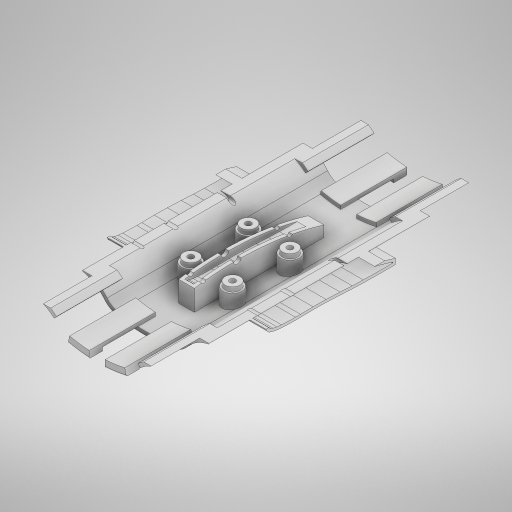
# Autodesk Inventor part: ENCASTRE_FUSELAJE
Saved by Autodesk Inventor 2023 (Build 270158000, 158)
## iProperties
Created: 2023-05-19
Part Number: ENCASTRE_FUSELAJE
Material: Genérico
Document SubType Name: Modeling
Designer: brand
Density: 1 g/cm^3
Appearance: Valor por defecto
Author: brand
Autodesk Inventor part; units mm, degrees
ref_plane "XZ Plane" through (0, 0, 0) normal (0, 1, 0) x (-1, 0, 0)
ref_plane "XY Plane" through (0, 0, 0) normal (0, 0, 1) x (1, 0, 0)
sketch "Boceto1" plane through (0, 0, 0) normal (0, 0, 1) x (1, 0, 0)
  line L0 (-27.5, 0) -> (27.5, 0) construction
  arc A0 (33, 24.3875) -> (-33, 24.3875) centre (0, -121.9375) ccw
  arc A1 (-33, -24.3875) -> (33, -24.3875) centre (0, 121.9375) ccw
  arc A2 (-70.9258, 0.9771) -> (-46.9085, 15.7579) centre (-80, 42.625) ccw
  arc A3 (-46.9085, -15.7579) -> (-70.9258, -0.9771) centre (-80, -42.625) ccw
  line L1 (0, 28.0625) -> (0, -28.0625) construction
  arc A4 (46.9085, 15.7579) -> (70.9258, 0.9771) centre (80, 42.625) ccw
  arc A5 (70.9258, -0.9771) -> (46.9085, -15.7579) centre (80, -42.625) ccw
  arc A6 (-33, 24.3875) -> (-46.9085, 15.7579) centre (-27.5, 0) ccw
  arc A7 (-46.9085, -15.7579) -> (-33, -24.3875) centre (-27.5, 0) ccw
  arc A8 (33, -24.3875) -> (46.9085, -15.7579) centre (27.5, 0) ccw
  arc A9 (46.9085, 15.7579) -> (33, 24.3875) centre (27.5, 0) ccw
  arc A10 (32.12, 20.4855) -> (-32.12, 20.4855) centre (0, -121.9375) ccw
  arc A11 (43.8031, 13.2366) -> (32.12, 20.4855) centre (27.5, 0) ccw
  arc A12 (43.8031, 13.2366) -> (61.1056, 0) centre (80, 42.625) ccw
  arc A13 (61.1056, 0) -> (43.8031, -13.2366) centre (80, -42.625) ccw
  arc A14 (32.12, -20.4855) -> (43.8031, -13.2366) centre (27.5, 0) ccw
  arc A15 (-32.12, -20.4855) -> (32.12, -20.4855) centre (0, 121.9375) ccw
  arc A16 (-43.8031, -13.2366) -> (-32.12, -20.4855) centre (-27.5, 0) ccw
  arc A17 (-43.8031, -13.2366) -> (-61.1056, 0) centre (-80, -42.625) ccw
  arc A18 (-61.1056, 0) -> (-43.8031, 13.2366) centre (-80, 42.625) ccw
  arc A19 (-32.12, 20.4855) -> (-43.8031, 13.2366) centre (-27.5, 0) ccw
  arc A20 (-70.9258, 0.9771) -> (-70.9258, -0.9771) centre (-70.7129, 0) ccw
  arc A21 (70.9258, -0.9771) -> (70.9258, 0.9771) centre (70.7129, 0) ccw
  point P0 (0, 0)
  point P1 (0, 0)
  point P2 (0, 0)
  dimension "d0" = 300
  dimension "d1" = 55
  dimension "d2" = 80
  dimension "d3" = 80
  dimension "d4" = 4
  dimension "d5" = 1
  constraints: 46 point on circle, 22 centre point, 6 tangent, 5 symmetric about line, 4 end point, 2 horizontal alignment, 1 coincident, 1 equal radius, 1 horizontal, 1 midpoint, 9 other
  measures "d0" diameter of A0
  measures "d1" distance of L0.start L0.end
  measures "d2" horizontal distance of point (0, 0) A18.centre
  measures "d3" horizontal distance of point (0, 0) A17.centre
  measures "d4" radial gap between concentric circles of A0 A10
  measures "d5" radius of A20
extrude "Extrusión1" add sketch "Boceto1" against normal blind 170
sketch "Boceto2" plane through (0, 0, 0) normal (1, 0, 0) x (0, 1, 0)
  arc A0 (-6.3235, -149.5277) -> (5.972, -101.1613) centre (-420.6839, -18.4451) ccw
  arc A1 (5.972, -101.1613) -> (11.3027, -54.4805) centre (-297.3284, -42.8809) ccw
  arc A2 (11.3027, -54.4805) -> (11.0641, -38.2325) centre (-144.1615, -48.6381) ccw
  arc A3 (11.0641, -38.2325) -> (7.9803, -20.5332) centre (-74.6379, -44.046) ccw
  arc A4 (7.9803, -20.5332) -> (5.1635, -13.545) centre (-27.6939, -30.851) ccw
  arc A5 (5.1635, -13.545) -> (2.6711, -10.3705) centre (-4.0493, -18.2127) ccw
  arc A6 (2.6711, -10.3705) -> (1.0881, -9.7136) centre (0.7764, -12.7005) ccw
  arc A7 (1.0881, -9.7136) -> (0, -10) centre (1.0887, -11.926) ccw
  arc A8 (0, -10) -> (-1.8033, -12.1262) centre (2.0348, -13.5536) ccw
  arc A9 (-1.8033, -12.1262) -> (-2.4847, -14.2967) centre (17.2896, -19.3122) ccw
  arc A10 (-2.4847, -14.2967) -> (-3.4173, -18.7476) centre (27.4031, -22.8823) ccw
  arc A11 (-3.4173, -18.7476) -> (-3.9308, -23.8416) centre (82.0127, -29.9326) ccw
  arc A12 (-3.9308, -23.8416) -> (-4.4581, -39.76) centre (210.5667, -38.9149) ccw
  line L0 (-4.4581, -39.76) -> (-4.4203, -45.4494)
  line L1 (-4.4203, -45.4494) -> (-4.1974, -59.6715)
  arc A13 (-4.3725, -74.4621) -> (-4.1974, -59.6715) centre (-320.6036, -63.321) ccw
  arc A14 (-5.0686, -90.3774) -> (-4.3725, -74.4621) centre (-890.267, -43.6885) ccw
  line L2 (-5.0686, -90.3774) -> (-5.78, -104.0138)
  arc A15 (-5.78, -104.0138) -> (-6.2063, -116.5233) centre (482.8669, -126.9256) ccw
  arc A16 (-6.2063, -116.5233) -> (-6.4633, -149.5204) centre (962.6143, -140.5689) ccw
  line L3 (-6.4633, -149.5204) -> (-6.3235, -149.5277)
  line L4 (0, 0) -> (0, -170) projected
  arc A17 (-4.4295, -23.8064) -> (-4.9581, -39.7626) centre (210.5667, -38.9149) ccw
  arc A18 (-3.9129, -18.6819) -> (-4.4295, -23.8064) centre (82.0127, -29.9326) ccw
  arc A19 (-2.9674, -14.1662) -> (-3.9129, -18.6819) centre (27.4031, -22.8823) ccw
  arc A20 (-2.2716, -11.951) -> (-2.9674, -14.1662) centre (17.2896, -19.3122) ccw
  arc A21 (-0.2473, -9.5654) -> (-2.2716, -11.951) centre (2.0348, -13.5536) ccw
  arc A22 (1.1143, -9.2137) -> (-0.2473, -9.5654) centre (1.0887, -11.926) ccw
  arc A23 (2.9917, -9.9868) -> (1.1143, -9.2137) centre (0.7764, -12.7005) ccw
  arc A24 (5.6077, -13.3155) -> (2.9917, -9.9868) centre (-4.0493, -18.2127) ccw
  arc A25 (8.4609, -20.3953) -> (5.6077, -13.3155) centre (-27.6939, -30.851) ccw
  arc A26 (11.563, -38.1989) -> (8.4609, -20.3953) centre (-74.6379, -44.046) ccw
  arc A27 (11.8023, -54.5016) -> (11.563, -38.1989) centre (-144.1615, -48.6381) ccw
  arc A28 (6.4629, -101.256) -> (11.8023, -54.5016) centre (-297.3284, -42.8809) ccw
  arc A29 (-5.9636, -150.0472) -> (6.4629, -101.256) centre (-420.6839, -18.4451) ccw
  line L5 (-5.9636, -150.0472) -> (-6.9588, -149.9951)
  arc A30 (-6.7061, -116.5118) -> (-6.9588, -149.9951) centre (962.6143, -140.5689) ccw
  arc A31 (-6.2794, -103.9891) -> (-6.7061, -116.5118) centre (482.8669, -126.9256) ccw
  line L6 (-6.2794, -103.9891) -> (-5.5679, -90.3513)
  arc A32 (-5.5679, -90.3513) -> (-4.8722, -74.4446) centre (-890.267, -43.6885) ccw
  arc A33 (-4.8722, -74.4446) -> (-4.6973, -59.6783) centre (-320.6036, -63.321) ccw
  line L7 (-4.6973, -59.6783) -> (-4.9203, -45.455)
  line L8 (-4.9203, -45.455) -> (-4.9581, -39.7626)
  line L9 (1.1143, -9.2137) -> (-24.0625, -9.2137) construction
  line L10 (-24.0625, -170) -> (-24.0625, 0) projected
  line L11 (-5.9636, -150.0472) -> (-24.0625, -150.0472) construction
  circle A34 centre (-336.4534, -54.4805) radius 340 construction
  line L12 (-24.0625, -6.2137) -> (24.3875, -6.2137)
  line L13 (24.3875, 0) -> (24.3875, -170) projected
  line L14 (-24.0625, -153.0472) -> (24.3875, -153.0472)
  circle A35 centre (1.7519, -16.7828) radius 2.25
  circle A36 centre (3.3626, -54.9049) radius 4.25
  circle A37 centre (-1.8171, -114.7492) radius 2.25
  point P0 (0, -10)
  dimension "d8" = 10
  dimension "d9" = 0.5
  dimension "d11" = 680
  dimension "d12" = 336.4534
  dimension "d13" = 54.4805
  dimension "d14" = 3
  dimension "d15" = 3
  dimension "d16" = 150.0472
  dimension "d19" = 4.5
  dimension "d20" = 8.5
  dimension "d21" = 4.5
  dimension "d22" = 16.7828
  dimension "d23" = 1.7519
  dimension "d24" = 54.9049
  dimension "d25" = 3.3626
  dimension "d26" = 114.7492
  dimension "d27" = 1.8171
  constraints: 68 point on circle, 38 centre point, 24 end point, 6 point on line, 3 horizontal, 1 perpendicular, 20 other
  measures "d8" distance of L4.start point (0, -10)
  measures "d9" radial gap between concentric circles of A12 A17
  measures "d11" diameter of A34
  measures "d12" horizontal distance of A34.centre L4.start
  measures "d13" vertical distance of A34.centre L4.start
  measures "d14" distance between parallel lines of L12 L9
  measures "d15" distance between parallel lines of L14 L11
  measures "d16" distance from line of L11 L4.start
  measures "d19" diameter of A35
  measures "d20" diameter of A36
  measures "d21" diameter of A37
  measures "d22" vertical distance of A35.centre L4.start
  measures "d23" horizontal distance of A35.centre L4.start
  measures "d24" vertical distance of A36.centre L4.start
  measures "d25" horizontal distance of A36.centre L4.start
  measures "d26" vertical distance of A37.centre L4.start
  measures "d27" horizontal distance of A37.centre L4.start
extrude "Extrusión2" add sketch "Boceto2" along normal mid plane 10 contours A29 A28 A27 A26 A25 A24 A23 A22 L4 L12 L13 L14 | L4 L14 L10 L12 A22 A21 A20 A19 A18 A17 L8 L7 A33 A32 L6 A31 A30 L5 A29
sketch "Boceto3" plane through (5, 0, 0) normal (1, 0, 0) x (0, 0, -1)
  line L0 (153.0472, 23.9769) -> (6.2137, 23.9769) projected
  line L1 (6.2137, -23.9769) -> (153.0472, -23.9769) projected
  line L2 (6.2137, -23.9769) -> (6.2137, 23.9769) projected
  line L3 (153.0472, 23.9769) -> (153.0472, -23.9769) projected
  circle A0 centre (16.783, 1.752) radius 2.6
  circle A1 centre (54.905, 3.363) radius 4.25
  circle A2 centre (114.749, -1.817) radius 2.6
  arc A3 (150.0472, -5.9636) -> (101.256, 6.4629) centre (18.4451, -420.6839) ccw projected
  arc A4 (101.256, 6.4629) -> (54.5016, 11.8023) centre (42.8809, -297.3284) ccw projected
  arc A5 (54.5016, 11.8023) -> (38.1989, 11.563) centre (48.6381, -144.1615) ccw projected
  arc A6 (38.1989, 11.563) -> (20.3953, 8.4609) centre (44.046, -74.6379) ccw projected
  arc A7 (20.3953, 8.4609) -> (13.3155, 5.6077) centre (30.851, -27.6939) ccw projected
  arc A8 (13.3155, 5.6077) -> (9.9868, 2.9917) centre (18.2127, -4.0493) ccw projected
  arc A9 (9.9868, 2.9917) -> (9.2137, 1.1143) centre (12.7005, 0.7764) ccw projected
  arc A10 (9.2137, 1.1143) -> (9.5654, -0.2473) centre (11.926, 1.0887) ccw projected
  arc A11 (9.5654, -0.2473) -> (11.951, -2.2716) centre (13.5536, 2.0348) ccw projected
  arc A12 (11.951, -2.2716) -> (14.1662, -2.9674) centre (19.3122, 17.2896) ccw projected
  arc A13 (14.1662, -2.9674) -> (18.6819, -3.9129) centre (22.8823, 27.4031) ccw projected
  arc A14 (18.6819, -3.9129) -> (23.8064, -4.4295) centre (29.9326, 82.0127) ccw projected
  arc A15 (23.8064, -4.4295) -> (39.7626, -4.9581) centre (38.9149, 210.5667) ccw projected
  arc A16 (150.0472, -5.9636) -> (101.256, 6.4629) centre (18.4451, -420.6839) ccw projected
  arc A17 (101.256, 6.4629) -> (54.5016, 11.8023) centre (42.8809, -297.3284) ccw projected
  arc A18 (54.5016, 11.8023) -> (38.1989, 11.563) centre (48.6381, -144.1615) ccw projected
  arc A19 (38.1989, 11.563) -> (20.3953, 8.4609) centre (44.046, -74.6379) ccw projected
  arc A20 (20.3953, 8.4609) -> (13.3155, 5.6077) centre (30.851, -27.6939) ccw projected
  arc A21 (13.3155, 5.6077) -> (9.9868, 2.9917) centre (18.2127, -4.0493) ccw projected
  arc A22 (9.9868, 2.9917) -> (9.2137, 1.1143) centre (12.7005, 0.7764) ccw projected
  arc A23 (9.2137, 1.1143) -> (9.5654, -0.2473) centre (11.926, 1.0887) ccw projected
  arc A24 (9.5654, -0.2473) -> (11.951, -2.2716) centre (13.5536, 2.0348) ccw projected
  arc A25 (11.951, -2.2716) -> (14.1662, -2.9674) centre (19.3122, 17.2896) ccw projected
  arc A26 (14.1662, -2.9674) -> (18.6819, -3.9129) centre (22.8823, 27.4031) ccw projected
  arc A27 (18.6819, -3.9129) -> (23.8064, -4.4295) centre (29.9326, 82.0127) ccw projected
  arc A28 (23.8064, -4.4295) -> (39.7626, -4.9581) centre (38.9149, 210.5667) ccw projected
  line L4 (39.7626, -4.9581) -> (45.455, -4.9203) projected
  line L5 (45.455, -4.9203) -> (59.6783, -4.6973) projected
  arc A29 (74.4446, -4.8722) -> (59.6783, -4.6973) centre (63.321, -320.6036) ccw projected
  arc A30 (90.3513, -5.5679) -> (74.4446, -4.8722) centre (43.6885, -890.267) ccw projected
  line L6 (90.3513, -5.5679) -> (103.9891, -6.2794) projected
  arc A31 (103.9891, -6.2794) -> (116.5118, -6.7061) centre (126.9256, 482.8669) ccw projected
  arc A32 (116.5118, -6.7061) -> (149.9951, -6.9588) centre (140.5689, 962.6143) ccw projected
  line L7 (149.9951, -6.9588) -> (150.0472, -5.9636) projected
  line L8 (153.0472, 23.9769) -> (6.2137, 23.9769) projected
  line L9 (153.0472, 23.9769) -> (153.0472, -23.9769) projected
  line L10 (6.2137, -23.9769) -> (153.0472, -23.9769) projected
  line L11 (6.2137, -23.9769) -> (6.2137, 23.9769) projected
  point P0 (0, 0)
  dimension "d28" = 5.2
  dimension "d29" = 8.5
  dimension "d30" = 5.2
  dimension "d31" = 16.783
  dimension "d32" = 1.752
  dimension "d33" = 3.363
  dimension "d34" = 54.905
  dimension "d35" = 114.749
  dimension "d36" = 1.817
  constraints: 3 centre point
  measures "d28" diameter of A0
  measures "d29" diameter of A1
  measures "d30" diameter of A2
  measures "d31" horizontal distance of point (0, 0) A0.centre
  measures "d32" vertical distance of point (0, 0) A0.centre
  measures "d33" vertical distance of point (0, 0) A1.centre
  measures "d34" horizontal distance of point (0, 0) A1.centre
  measures "d35" horizontal distance of point (0, 0) A2.centre
  measures "d36" vertical distance of point (0, 0) A2.centre
extrude "Extrusión3" add sketch "Boceto3" along normal blind 4 contours L3 L1 L2 L0 | L7 A32 A31 L6 A30 A29 L5 L4 A15 A14 A13 A12 A11 A10 A9 A8 A7 A6 A5 A4 A3
mirror "Simetría1" about plane through (0, 0, 0) normal (1, 0, 0) of "Extrusión3"
sketch "Boceto4" plane through (0, 0, 0) normal (1, 0, 0) x (0, 1, 0)
  circle A0 centre (1.752, -16.783) radius 2.6 projected
  circle A1 centre (3.363, -54.905) radius 4.25 projected
  circle A2 centre (-1.817, -114.749) radius 2.6 projected
  point P0 (0, 0)
extrude "Extrusión4" cut sketch "Boceto4" along normal through all both and the other way through all
sketch "Boceto5" plane through (0, 0, 0) normal (0, 1, 0) x (-1, 0, 0)
  circle A0 centre (-23.62, -99.8876) radius 8.5
  line L0 (32.12, -170) -> (-32.12, -170) projected
  line L1 (-33, -170) -> (33, -170) projected
  line L2 (0, -170) -> (0, 0)
  line L3 (9, -153.0472) -> (-9, -153.0472) projected
  line L4 (-9, -153.0472) -> (-9, -6.2137) projected
  line L5 (-9, -6.2137) -> (9, -6.2137) projected
  line L6 (9, -6.2137) -> (9, -153.0472) projected
  line L7 (-32.12, 0) -> (32.12, 0) projected
  line L8 (-32.12, 0) -> (-32.12, -170) projected
  line L9 (32.12, -170) -> (-32.12, -170) projected
  line L10 (32.12, 0) -> (32.12, -170) projected
  circle A1 centre (-23.62, -34.8116) radius 8.5
  circle A2 centre (23.62, -99.8876) radius 8.5
  circle A3 centre (23.62, -34.8116) radius 8.5
  circle A4 centre (-23.62, -99.8876) radius 3.25
  circle A5 centre (-23.62, -34.8116) radius 3.25
  circle A6 centre (23.62, -99.8876) radius 3.25
  circle A7 centre (23.62, -34.8116) radius 3.25
  dimension "d41" = 17
  dimension "d42" = 6.5
  dimension "d43" = 6.5
  constraints: 8 centre point, 4 symmetric about line, 2 coincident, 2 end point, 2 tangent, 1 equal radius, 1 midpoint, 1 vertical, 4 other
  measures "d41" diameter of A0
  measures "d42" diameter of A4
  measures "d43" diameter of A5
extrude "Extrusión5" add sketch "Boceto5" along normal mid plane 20 contours A0 | A1 | A2 | A3
sketch "Boceto6" plane through (23.62, 10, -34.8116) normal (0, 1, 0) x (1, 0, 0)
  circle A0 centre (0, 0) radius 3.25 projected
  line L0 (-3.1754, 5.5) -> (3.1754, 5.5)
  line L1 (3.1754, 5.5) -> (6.3509, 0)
  line L2 (6.3509, 0) -> (3.1754, -5.5)
  line L3 (3.1754, -5.5) -> (-3.1754, -5.5)
  line L4 (-3.1754, -5.5) -> (-6.3509, 0)
  line L5 (-6.3509, 0) -> (-3.1754, 5.5)
  circle A1 centre (0, 0) radius 10.5
  line L6 (-23.62, -34.8116) -> (-23.62, 135.1884)
  line L7 (9.38, 135.1884) -> (-56.62, 135.1884) projected
  circle A2 centre (0, 65.076) radius 3.25 projected
  line L8 (0, 65.076) -> (0, 0)
  line L9 (0, 32.538) -> (-50.0066, 32.538)
  circle A3 centre (0, 65.076) radius 3.25
  line L10 (-3.1754, 59.576) -> (3.1754, 59.576)
  line L11 (3.1754, 59.576) -> (6.3509, 65.076)
  line L12 (6.3509, 65.076) -> (3.1754, 70.576)
  line L13 (3.1754, 70.576) -> (-3.1754, 70.576)
  line L14 (-3.1754, 70.576) -> (-6.3509, 65.076)
  line L15 (-6.3509, 65.076) -> (-3.1754, 59.576)
  circle A4 centre (0, 65.076) radius 10.5
  circle A5 centre (-47.24, 0) radius 3.25
  line L16 (-44.0646, 5.5) -> (-50.4154, 5.5)
  line L17 (-50.4154, 5.5) -> (-53.5909, 0)
  line L18 (-53.5909, 0) -> (-50.4154, -5.5)
  line L19 (-50.4154, -5.5) -> (-44.0646, -5.5)
  line L20 (-44.0646, -5.5) -> (-40.8891, 0)
  line L21 (-40.8891, 0) -> (-44.0646, 5.5)
  circle A6 centre (-47.24, 0) radius 10.5
  circle A7 centre (-47.24, 65.076) radius 3.25
  line L22 (-47.24, 65.076) -> (-47.24, 0)
  line L23 (-50.4154, 59.576) -> (-53.5909, 65.076)
  line L24 (-40.8891, 65.076) -> (-44.0646, 59.576)
  circle A8 centre (-47.24, 65.076) radius 3.25
  line L25 (-53.5909, 65.076) -> (-50.4154, 70.576)
  line L26 (-50.4154, 70.576) -> (-44.0646, 70.576)
  line L27 (-44.0646, 70.576) -> (-40.8891, 65.076)
  circle A9 centre (-47.24, 65.076) radius 10.5
  line L28 (-44.0646, 59.576) -> (-50.4154, 59.576)
  point P0 (0, 5.5)
  point P1 (0, 59.576)
  point P2 (-47.24, 5.5)
  point P3 (-47.24, 32.538)
  point P4 (-47.24, 59.576)
  dimension "d46" = 11
  dimension "d47" = 11
  dimension "d48" = 11
  dimension "d49" = 120
  dimension "d50" = 120
  dimension "d51" = 21
  constraints: 56 end point, 27 symmetric about line, 8 centre point, 4 coincident, 3 midpoint, 3 parallel, 2 horizontal, 1 equal length, 1 horizontal alignment, 1 vertical, 1 vertical alignment, 7 other
  measures "d46" distance between parallel lines of L3 L0
  measures "d47" distance between parallel lines of L4 L1
  measures "d48" distance between parallel lines of L5 L2
  measures "d49" angle of L5 L0
  measures "d50" angle of L2 L1
  measures "d51" diameter of A1
extrude "Extrusión6" add sketch "Boceto6" along normal through all contours A1 | A4 | A6 | A9
sketch "Boceto7" plane through (-23.62, 10, -34.8116) normal (0, -1, 0) x (1, 0, 0)
  line L0 (-6.3509, 0) -> (-3.1754, -5.5) projected
  line L1 (-3.1754, -5.5) -> (3.1754, -5.5) projected
  line L2 (3.1754, -5.5) -> (6.3509, 0) projected
  line L3 (6.3509, 0) -> (3.1754, 5.5) projected
  line L4 (3.1754, 5.5) -> (-3.1754, 5.5) projected
  line L5 (-3.1754, 5.5) -> (-6.3509, 0) projected
  line L6 (40.8891, 0) -> (44.0646, -5.5) projected
  line L7 (44.0646, -5.5) -> (50.4154, -5.5) projected
  line L8 (50.4154, -5.5) -> (53.5909, 0) projected
  line L9 (53.5909, 0) -> (50.4154, 5.5) projected
  line L10 (50.4154, 5.5) -> (44.0646, 5.5) projected
  line L11 (44.0646, 5.5) -> (40.8891, 0) projected
  line L12 (53.5909, -65.076) -> (50.4154, -59.576) projected
  line L13 (50.4154, -59.576) -> (44.0646, -59.576) projected
  line L14 (44.0646, -59.576) -> (40.8891, -65.076) projected
  line L15 (40.8891, -65.076) -> (44.0646, -70.576) projected
  line L16 (44.0646, -70.576) -> (50.4154, -70.576) projected
  line L17 (50.4154, -70.576) -> (53.5909, -65.076) projected
  line L18 (6.3509, -65.076) -> (3.1754, -59.576) projected
  line L19 (3.1754, -59.576) -> (-3.1754, -59.576) projected
  line L20 (-3.1754, -59.576) -> (-6.3509, -65.076) projected
  line L21 (-6.3509, -65.076) -> (-3.1754, -70.576) projected
  line L22 (-3.1754, -70.576) -> (3.1754, -70.576) projected
  line L23 (3.1754, -70.576) -> (6.3509, -65.076) projected
  point P0 (23.62, 34.8116)
extrude "Extrusión7" cut sketch "Boceto7" against normal through all
sketch "Boceto8" plane through (-23.62, -10, -34.8116) normal (0, -1, 0) x (1, 0, 0)
  circle A0 centre (0, 0) radius 10.5 projected
  circle A1 centre (0, 0) radius 8.5 projected
  circle A2 centre (47.24, 0) radius 10.5 projected
  circle A3 centre (47.24, 0) radius 8.5 projected
  circle A4 centre (47.24, -65.076) radius 10.5 projected
  circle A5 centre (47.24, -65.076) radius 8.5 projected
  circle A6 centre (0, -65.076) radius 10.5 projected
  circle A7 centre (0, -65.076) radius 8.5 projected
  point P0 (23.62, 34.8116)
extrude "Extrusión8" add sketch "Boceto8" against normal blind 5
sketch "Boceto9" plane through (-23.62, -10, -34.8116) normal (0, -1, 0) x (1, 0, 0)
  circle A0 centre (0, 0) radius 8.5 projected
  circle A1 centre (47.24, 0) radius 8.5 projected
  circle A2 centre (47.24, -65.076) radius 8.5 projected
  circle A3 centre (0, -65.076) radius 8.5 projected
  point P0 (23.62, 34.8116)
extrude "Extrusión9" cut sketch "Boceto9" along normal through all
sketch "Boceto10" plane through (-23.62, -10, -34.8116) normal (0, -1, 0) x (1, 0, 0)
  circle A0 centre (0, 0) radius 10.5 projected
  circle A1 centre (47.24, 0) radius 10.5 projected
  circle A2 centre (0, -65.076) radius 10.5 projected
  circle A3 centre (47.24, -65.076) radius 10.5 projected
  circle A4 centre (0, 0) radius 8.5 projected
  circle A5 centre (47.24, 0) radius 10.5 projected
  circle A6 centre (47.24, 0) radius 8.5 projected
  circle A7 centre (47.24, -65.076) radius 10.5 projected
  circle A8 centre (47.24, -65.076) radius 8.5 projected
  circle A9 centre (0, -65.076) radius 10.5 projected
  circle A10 centre (0, -65.076) radius 8.5 projected
  point P0 (23.62, 34.8116)
extrude "Extrusión10" add sketch "Boceto10" along normal through all
sketch "Boceto11" plane through (0, 0, 0) normal (0, 0, 1) x (1, 0, 0)
  line L0 (9, 23.7849) -> (9, -23.7849) projected
  line L1 (-9, 23.7849) -> (-9, -23.7849) projected
  line L2 (9, -23.7849) -> (9, 23.7849) projected
  line L3 (9, 0) -> (83.9061, 0)
  line L4 (83.9061, 0) -> (83.9061, 38.5054)
  line L5 (83.9061, 38.5054) -> (-83.4412, 38.5054)
  line L6 (-83.4412, 38.5054) -> (-83.4412, 0)
  line L7 (-83.4412, 0) -> (-9, 0)
  line L8 (-9, -23.7849) -> (-9, 23.7849) projected
  arc A0 (9, 23.7849) -> (-9, 23.7849) centre (0, -121.9375) ccw projected
  line L9 (-9, 23.7849) -> (-9, -23.7849) projected
  arc A1 (-9, -23.7849) -> (9, -23.7849) centre (0, 121.9375) ccw projected
  line L10 (9, 23.7849) -> (9, -23.7849) projected
  point P0 (0, 0)
  point P1 (-9, 0)
  constraints: 10 end point, 3 perpendicular, 2 midpoint, 1 horizontal, 1 point on line
extrude "Extrusión11" cut sketch "Boceto11" against normal through all contours A0 L1 L7 L6 L5 L4 L3 L0
sketch "Boceto12" plane through (9, 0, 0) normal (1, 0, 0) x (0, 0, -1)
  circle A0 centre (54.481, -336.9415) radius 340
  line L0 (0, 0) -> (0, -0.9771) projected
  line L1 (153.0472, 24.0625) -> (6.2137, 24.0625) projected
  line L2 (6.2137, 23.7849) -> (6.2137, 24.0625) projected
  line L3 (6.2137, 23.7849) -> (6.2137, -23.7849) projected
  line L4 (153.0472, 24.0625) -> (153.0472, 23.7849) projected
  line L5 (153.0472, -23.7849) -> (153.0472, 23.7849) projected
  point P0 (0, -0.4885)
  point P1 (0, -0.4885)
  point P2 (6.2137, -0.3851)
  point P3 (153.0472, -11.5422)
  dimension "d64" = 680
  dimension "d65" = 336.453
  dimension "d66" = 54.481
  constraints: 2 midpoint, 1 centre point
  measures "d64" diameter of A0
  measures "d65" vertical distance of point (0, -0.489) A0.centre
  measures "d66" horizontal distance of point (0, -0.489) A0.centre
extrude "Extrusión12" cut sketch "Boceto12" against normal up to surface (18 mm away) contours A0 L3 L2 L1 L4 L5
ref_plane "Plano de trabajo1" through (90, 0, 0) normal (1, 0, 0) x (0, 1, 0)
sketch "Boceto16" plane through (90, 0, 0) normal (1, 0, 0) x (0, 1, 0)
  arc A0 (0.6889, -14.4103) -> (0.0588, -9.4167) centre (-336.9415, -54.481) ccw projected
  arc A1 (0.0588, -9.4167) -> (-0.2473, -9.5654) centre (1.0887, -11.926) ccw projected
  arc A2 (-0.2473, -9.5654) -> (-2.2716, -11.951) centre (2.0348, -13.5536) ccw projected
  arc A3 (-2.2716, -11.951) -> (-2.9674, -14.1662) centre (17.2896, -19.3122) ccw projected
  arc A4 (-2.9674, -14.1662) -> (-3.9129, -18.6819) centre (27.4031, -22.8823) ccw projected
  arc A5 (-3.9129, -18.6819) -> (-4.4295, -23.8064) centre (82.0127, -29.9326) ccw projected
  arc A6 (-4.4295, -23.8064) -> (-4.9581, -39.7626) centre (210.5667, -38.9149) ccw projected
  line L0 (-4.9581, -39.7626) -> (-4.9203, -45.455) projected
  line L1 (-4.9203, -45.455) -> (-4.6973, -59.6783) projected
  arc A7 (-4.8722, -74.4446) -> (-4.6973, -59.6783) centre (-320.6036, -63.321) ccw projected
  arc A8 (-5.5679, -90.3513) -> (-4.8722, -74.4446) centre (-890.267, -43.6885) ccw projected
  line L2 (-5.5679, -90.3513) -> (-6.2794, -103.9891) projected
  arc A9 (-6.2794, -103.9891) -> (-6.7061, -116.5118) centre (482.8669, -126.9256) ccw projected
  arc A10 (-6.7061, -116.5118) -> (-6.9963, -136.555) centre (962.6143, -140.5689) ccw projected
  arc A11 (-6.9963, -136.555) -> (-2.7704, -117.1679) centre (-336.9415, -54.481) ccw projected
  arc A12 (-1.8679, -112.1495) -> (-2.7704, -117.1679) centre (-1.817, -114.749) ccw projected
  arc A13 (-1.8679, -112.1495) -> (3.0265, -59.1417) centre (-336.9415, -54.481) ccw projected
  arc A14 (3.0371, -50.6675) -> (3.0265, -59.1417) centre (3.363, -54.905) ccw projected
  arc A15 (3.0371, -50.6675) -> (1.2367, -19.3314) centre (-336.9415, -54.481) ccw projected
  arc A16 (0.6889, -14.4103) -> (1.2367, -19.3314) centre (1.752, -16.783) ccw projected
  arc A17 (11.0618, -38.2944) -> (7.978, -20.595) centre (-74.6402, -44.1079) ccw
  arc A18 (7.978, -20.595) -> (5.1612, -13.6069) centre (-27.6962, -30.9129) ccw
  arc A19 (5.1612, -13.6069) -> (2.6688, -10.4324) centre (-4.0517, -18.2746) ccw
  arc A20 (2.6688, -10.4324) -> (0.6236, -9.763) centre (0.7741, -12.7624) ccw
  arc A21 (0.6236, -9.763) -> (0, -10) centre (1.0887, -11.926) ccw
  line L3 (-6.4633, -149.5204) -> (-6.3235, -149.5277)
  arc A22 (-4.4295, -23.8064) -> (-4.9581, -39.7626) centre (210.5667, -38.9149) ccw
  arc A23 (-3.9129, -18.6819) -> (-4.4295, -23.8064) centre (82.0127, -29.9326) ccw
  arc A24 (-2.9674, -14.1662) -> (-3.9129, -18.6819) centre (27.4031, -22.8823) ccw
  arc A25 (-2.2716, -11.951) -> (-2.9674, -14.1662) centre (17.2896, -19.3122) ccw
  arc A26 (-0.2473, -9.5654) -> (-2.2716, -11.951) centre (2.0348, -13.5536) ccw
  arc A27 (0.5586, -9.2659) -> (-0.2473, -9.5654) centre (1.0887, -11.926) ccw
  arc A28 (2.9894, -10.0487) -> (0.5586, -9.2659) centre (0.7741, -12.7624) ccw
  arc A29 (5.6054, -13.3773) -> (2.9894, -10.0487) centre (-4.0517, -18.2746) ccw
  arc A30 (8.4586, -20.4571) -> (5.6054, -13.3773) centre (-27.6962, -30.9129) ccw
  arc A31 (11.5606, -38.2608) -> (8.4586, -20.4571) centre (-74.6402, -44.1079) ccw
  arc A32 (11.8023, -54.501) -> (11.5606, -38.2608) centre (-144.1638, -48.7) ccw
  arc A33 (6.4629, -101.256) -> (11.8023, -54.501) centre (-297.3284, -42.8809) ccw
  arc A34 (-5.9636, -150.0472) -> (6.4629, -101.256) centre (-420.6839, -18.4451) ccw
  line L4 (-5.9636, -150.0472) -> (-6.9588, -149.9951)
  arc A35 (-6.7061, -116.5118) -> (-6.9588, -149.9951) centre (962.6143, -140.5689) ccw
  arc A36 (-6.2794, -103.9891) -> (-6.7061, -116.5118) centre (482.8669, -126.9256) ccw
  line L5 (-6.2794, -103.9891) -> (-5.5679, -90.3513)
  arc A37 (-5.5679, -90.3513) -> (-4.8722, -74.4446) centre (-890.267, -43.6885) ccw
  arc A38 (-4.8722, -74.4446) -> (-4.6973, -59.6783) centre (-320.6036, -63.321) ccw
  line L6 (-4.6973, -59.6783) -> (-4.9203, -45.455)
  line L7 (-4.9203, -45.455) -> (-4.9581, -39.7626)
  line L8 (0.5586, -9.2659) -> (-24.6182, -9.2659) construction
  line L9 (-5.9636, -150.0472) -> (-24.0625, -150.0472) construction
  circle A39 centre (-336.4534, -54.4805) radius 340 construction
  line L10 (-24.6182, -6.2659) -> (23.8318, -6.2659)
  line L11 (-24.0625, -153.0472) -> (24.3875, -153.0472)
  circle A40 centre (1.7519, -16.7828) radius 2.25
  circle A41 centre (3.3626, -54.9049) radius 4.25
  circle A42 centre (-1.8171, -114.7492) radius 2.25
  line L12 (0, 0) -> (0, -14.8619) projected
  line L13 (0, 0) -> (0, -169.9982)
  arc A43 (-7.8704, -74.3397) -> (-7.6971, -59.7191) centre (-320.6036, -63.321) ccw
  arc A44 (-8.5638, -90.1941) -> (-7.8704, -74.3397) centre (-890.267, -43.6885) ccw
  line L14 (-8.5638, -90.1941) -> (-9.2758, -103.8407)
  arc A45 (-9.2758, -103.8407) -> (-9.7053, -116.4427) centre (482.8669, -126.9256) ccw
  arc A46 (-9.7053, -116.4427) -> (-9.9272, -152.8436) centre (962.6143, -140.5689) ccw
  line L15 (-9.9272, -152.8436) -> (-3.8117, -153.1641)
  arc A47 (-3.8117, -153.1641) -> (9.4086, -101.8246) centre (-420.6839, -18.4451) ccw
  arc A48 (9.4086, -101.8246) -> (14.8002, -54.6131) centre (-297.3284, -42.8809) ccw
  arc A49 (14.8002, -54.6131) -> (14.5538, -38.059) centre (-144.1638, -48.7) ccw
  arc A50 (14.5538, -38.059) -> (11.3423, -19.6299) centre (-74.6402, -44.1079) ccw
  arc A51 (11.3423, -19.6299) -> (8.2702, -11.9991) centre (-27.6962, -30.9129) ccw
  arc A52 (8.2702, -11.9991) -> (4.9161, -7.749) centre (-4.0517, -18.2746) ccw
  arc A53 (4.9161, -7.749) -> (0.1782, -6.2866) centre (0.7741, -12.7624) ccw
  arc A54 (0.1782, -6.2866) -> (-1.7315, -6.9583) centre (1.0887, -11.926) ccw
  arc A55 (-1.7315, -6.9583) -> (-5.0811, -10.8991) centre (2.0348, -13.5536) ccw
  arc A56 (-5.0811, -10.8991) -> (-5.8635, -13.3824) centre (17.2896, -19.3122) ccw
  arc A57 (-5.8635, -13.3824) -> (-6.8869, -18.2878) centre (27.4031, -22.8823) ccw
  arc A58 (-6.8869, -18.2878) -> (-7.4221, -23.5952) centre (82.0127, -29.9326) ccw
  arc A59 (-7.4221, -23.5952) -> (-7.9581, -39.7785) centre (210.5667, -38.9149) ccw
  line L16 (-7.9581, -39.7785) -> (-7.9201, -45.4884)
  line L17 (-7.9201, -45.4884) -> (-7.6971, -59.7191)
  point P0 (0, -10)
  point P1 (-6.9161, -127.4703)
  point P2 (0, -9.4417)
  point P3 (0, -6.3183)
  point P4 (-6.0421, -153.0472)
  point P5 (-3.7739, -153.0472)
  point P6 (0, -140.7428)
  point P7 (0, -129.5177)
  dimension "d78" = 680
  dimension "d79" = 3
  dimension "d80" = 3
  dimension "d81" = 4.5
  dimension "d82" = 8.5
  dimension "d83" = 4.5
  dimension "d84" = 3
  constraints: 78 point on circle, 43 centre point, 28 end point, 3 horizontal, 1 vertical, 24 other
  measures "d78" diameter of A39
  measures "d79" distance between parallel lines of L10 L8
  measures "d80" distance between parallel lines of L11 L9
  measures "d81" diameter of A40
  measures "d82" diameter of A41
  measures "d83" diameter of A42
  measures "d84" radial gap between concentric circles of A38 A43
extrude "Extrusión16" add sketch "Boceto16" against normal up to surface contours A1 A2 A3 A4 A5 A6 L0 L1 A7 A8 L2 A9 A10 A35 L4 A34 L13 A47 L11 L15 A46 A45 L14 A44 A43 L17 L16 A59 A58 A57 A56 A55 A54 L12 round surface about axis through (80, -42.625, 0) along (0, 0, -1) radius 42.625 far side no
sketch "Boceto17" plane through (90, 0, 0) normal (1, 0, 0) x (0, 0, -1)
  arc A0 (9.5654, -0.2473) -> (11.951, -2.2716) centre (13.5536, 2.0348) ccw projected
  arc A1 (9.4417, 0) -> (9.5654, -0.2473) centre (11.926, 1.0887) ccw projected
  line L0 (9.4417, 0) -> (6.3183, 0) projected
  arc A2 (6.3183, 0) -> (6.9583, -1.7315) centre (11.926, 1.0887) ccw projected
  arc A3 (6.9583, -1.7315) -> (10.8991, -5.0811) centre (13.5536, 2.0348) ccw projected
  arc A4 (10.8991, -5.0811) -> (13.3824, -5.8635) centre (19.3122, 17.2896) ccw projected
  arc A5 (13.3824, -5.8635) -> (18.2878, -6.8869) centre (22.8823, 27.4031) ccw projected
  arc A6 (18.2878, -6.8869) -> (23.5952, -7.4221) centre (29.9326, 82.0127) ccw projected
  arc A7 (23.5952, -7.4221) -> (39.7785, -7.9581) centre (38.9149, 210.5667) ccw projected
  line L1 (39.7785, -7.9581) -> (45.4884, -7.9201) projected
  line L2 (45.4884, -7.9201) -> (59.7191, -7.6971) projected
  arc A8 (74.3397, -7.8704) -> (59.7191, -7.6971) centre (63.321, -320.6036) ccw projected
  arc A9 (90.1941, -8.5638) -> (74.3397, -7.8704) centre (43.6885, -890.267) ccw projected
  line L3 (90.1941, -8.5638) -> (103.8407, -9.2758) projected
  arc A10 (103.8407, -9.2758) -> (116.4427, -9.7053) centre (126.9256, 482.8669) ccw projected
  arc A11 (116.4427, -9.7053) -> (152.8436, -9.9272) centre (140.5689, 962.6143) ccw projected
  line L4 (152.8436, -9.9272) -> (153.0472, -6.0421) projected
  line L5 (153.0472, -6.0421) -> (153.0472, -3.7739) projected
  arc A12 (153.0472, -3.7739) -> (140.7428, 0) centre (18.4451, -420.6839) ccw projected
  line L6 (140.7428, 0) -> (129.5177, 0) projected
  arc A13 (150.0472, -5.9636) -> (129.5177, 0) centre (18.4451, -420.6839) ccw projected
  line L7 (150.0472, -5.9636) -> (149.9951, -6.9588) projected
  arc A14 (116.5118, -6.7061) -> (149.9951, -6.9588) centre (140.5689, 962.6143) ccw projected
  arc A15 (103.9891, -6.2794) -> (116.5118, -6.7061) centre (126.9256, 482.8669) ccw projected
  line L8 (103.9891, -6.2794) -> (90.3513, -5.5679) projected
  arc A16 (90.3513, -5.5679) -> (74.4446, -4.8722) centre (43.6885, -890.267) ccw projected
  arc A17 (74.4446, -4.8722) -> (59.6783, -4.6973) centre (63.321, -320.6036) ccw projected
  line L9 (59.6783, -4.6973) -> (45.455, -4.9203) projected
  line L10 (45.455, -4.9203) -> (39.7626, -4.9581) projected
  arc A18 (23.8064, -4.4295) -> (39.7626, -4.9581) centre (38.9149, 210.5667) ccw projected
  arc A19 (18.6819, -3.9129) -> (23.8064, -4.4295) centre (29.9326, 82.0127) ccw projected
  arc A20 (14.1662, -2.9674) -> (18.6819, -3.9129) centre (22.8823, 27.4031) ccw projected
  arc A21 (11.951, -2.2716) -> (14.1662, -2.9674) centre (19.3122, 17.2896) ccw projected
  point P0 (0, 0)
extrude "Extrusión17" add sketch "Boceto17" against normal blind 28.75
mirror "Simetría4" about plane through (0, 0, 0) normal (1, 0, 0) of "Extrusión16", "Extrusión17"
sketch "Boceto18" plane through (0, 0, 0) normal (0, 0, 1) x (1, 0, 0)
  line L0 (71.7129, 0) -> (61.1056, 0) projected
  arc A0 (61.1056, 0) -> (43.8031, -13.2366) centre (80, -42.625) ccw projected
  arc A1 (32.12, -20.4855) -> (43.8031, -13.2366) centre (27.5, 0) ccw projected
  arc A2 (-32.12, -20.4855) -> (32.12, -20.4855) centre (0, 121.9375) ccw projected
  arc A3 (-43.8031, -13.2366) -> (-32.12, -20.4855) centre (-27.5, 0) ccw projected
  arc A4 (-43.8031, -13.2366) -> (-61.1056, 0) centre (-80, -42.625) ccw projected
  line L1 (-61.1056, 0) -> (-71.7129, 0) projected
  arc A5 (-71.7129, 0) -> (-70.9258, -0.9771) centre (-70.7129, 0) ccw projected
  arc A6 (-46.9085, -15.7579) -> (-70.9258, -0.9771) centre (-80, -42.625) ccw projected
  arc A7 (-46.9085, -15.7579) -> (-33, -24.3875) centre (-27.5, 0) ccw projected
  arc A8 (-33, -24.3875) -> (33, -24.3875) centre (0, 121.9375) ccw projected
  arc A9 (33, -24.3875) -> (46.9085, -15.7579) centre (27.5, 0) ccw projected
  arc A10 (70.9258, -0.9771) -> (46.9085, -15.7579) centre (80, -42.625) ccw projected
  arc A11 (70.9258, -0.9771) -> (71.7129, 0) centre (70.7129, 0) ccw projected
  point P0 (0, 0)
extrude "Extrusión18" add sketch "Boceto18" along normal blind 40
sketch "Boceto19" plane through (0, 0, -170) normal (0, 0, -1) x (-1, 0, 0)
  line L0 (-61.1056, 0) -> (-71.7129, 0) projected
  arc A0 (-71.7129, 0) -> (-70.9258, -0.9771) centre (-70.7129, 0) ccw projected
  arc A1 (-46.9085, -15.7579) -> (-70.9258, -0.9771) centre (-80, -42.625) ccw projected
  arc A2 (-46.9085, -15.7579) -> (-33, -24.3875) centre (-27.5, 0) ccw projected
  arc A3 (-33, -24.3875) -> (33, -24.3875) centre (0, 121.9375) ccw projected
  arc A4 (33, -24.3875) -> (46.9085, -15.7579) centre (27.5, 0) ccw projected
  arc A5 (70.9258, -0.9771) -> (46.9085, -15.7579) centre (80, -42.625) ccw projected
  arc A6 (70.9258, -0.9771) -> (71.7129, 0) centre (70.7129, 0) ccw projected
  line L1 (71.7129, 0) -> (61.1056, 0) projected
  arc A7 (61.1056, 0) -> (43.8031, -13.2366) centre (80, -42.625) ccw projected
  arc A8 (32.12, -20.4855) -> (43.8031, -13.2366) centre (27.5, 0) ccw projected
  arc A9 (-32.12, -20.4855) -> (32.12, -20.4855) centre (0, 121.9375) ccw projected
  arc A10 (-43.8031, -13.2366) -> (-32.12, -20.4855) centre (-27.5, 0) ccw projected
  arc A11 (-43.8031, -13.2366) -> (-61.1056, 0) centre (-80, -42.625) ccw projected
  point P0 (0, 0)
extrude "Extrusión19" add sketch "Boceto19" along normal blind 40
sketch "Boceto20" plane through (0, 0, 40) normal (0, 0, 1) x (1, 0, 0)
  line L0 (71.7129, 0) -> (61.1056, 0) projected
  arc A0 (61.1056, 0) -> (43.8031, -13.2366) centre (80, -42.625) ccw projected
  arc A1 (32.12, -20.4855) -> (43.8031, -13.2366) centre (27.5, 0) ccw projected
  arc A2 (-32.12, -20.4855) -> (32.12, -20.4855) centre (0, 121.9375) ccw projected
  arc A3 (-43.8031, -13.2366) -> (-32.12, -20.4855) centre (-27.5, 0) ccw projected
  arc A4 (-43.8031, -13.2366) -> (-61.1056, 0) centre (-80, -42.625) ccw projected
  line L1 (-61.1056, 0) -> (-71.7129, 0) projected
  arc A5 (-71.7129, 0) -> (-70.9258, -0.9771) centre (-70.7129, 0) ccw projected
  arc A6 (-46.9085, -15.7579) -> (-70.9258, -0.9771) centre (-80, -42.625) ccw projected
  arc A7 (-46.9085, -15.7579) -> (-33, -24.3875) centre (-27.5, 0) ccw projected
  arc A8 (-33, -24.3875) -> (33, -24.3875) centre (0, 121.9375) ccw projected
  arc A9 (33, -24.3875) -> (46.9085, -15.7579) centre (27.5, 0) ccw projected
  arc A10 (70.9258, -0.9771) -> (46.9085, -15.7579) centre (80, -42.625) ccw projected
  arc A11 (70.9258, -0.9771) -> (71.7129, 0) centre (70.7129, 0) ccw projected
  arc A12 (31.24, -16.5835) -> (40.6978, -10.7153) centre (27.5, 0) ccw
  arc A13 (60.2769, 4) -> (40.6978, -10.7153) centre (80, -42.625) ccw
  line L2 (60.2769, 4) -> (73.7129, 4)
  arc A14 (71.7773, -4.8854) -> (73.7129, 4) centre (70.7129, 0) ccw
  arc A15 (71.7773, -4.8854) -> (50.0139, -18.2791) centre (80, -42.625) ccw
  arc A16 (33.88, -28.2895) -> (50.0139, -18.2791) centre (27.5, 0) ccw
  arc A17 (-33.88, -28.2895) -> (33.88, -28.2895) centre (0, 121.9375) ccw
  arc A18 (-50.0139, -18.2791) -> (-33.88, -28.2895) centre (-27.5, 0) ccw
  arc A19 (-50.0139, -18.2791) -> (-71.7773, -4.8854) centre (-80, -42.625) ccw
  arc A20 (-73.7129, 4) -> (-71.7773, -4.8854) centre (-70.7129, 0) ccw
  line L3 (-73.7129, 4) -> (-60.2769, 4)
  arc A21 (-40.6978, -10.7153) -> (-60.2769, 4) centre (-80, -42.625) ccw
  arc A22 (-40.6978, -10.7153) -> (-31.24, -16.5835) centre (-27.5, 0) ccw
  arc A23 (-31.24, -16.5835) -> (31.24, -16.5835) centre (0, 121.9375) ccw
  arc A24 (-32.12, -20.4855) -> (32.12, -20.4855) centre (0, 121.9375) ccw projected
  line L4 (-32.12, -20.4855) -> (-31.24, -16.5835)
  line L5 (-9, -23.7849) -> (-9, -19.777)
  line L6 (-9, -23.7849) -> (-9, -11.5422) projected
  line L7 (9, -0.3851) -> (9, -23.7849) projected
  line L8 (9, -19.777) -> (9, -23.7849)
  arc A25 (32.12, -20.4855) -> (43.8031, -13.2366) centre (27.5, 0) ccw projected
  line L9 (32.12, -20.4855) -> (31.24, -16.5835)
  arc A26 (-43.8031, -13.2366) -> (-61.1056, 0) centre (-80, -42.625) ccw projected
  line L10 (-61.1056, 0) -> (-52.687, 0)
  line L11 (-46.1289, -5) -> (-48.8052, -7.9728)
  line L12 (61.1056, 0) -> (52.687, 0)
  line L13 (46.1289, -5) -> (48.8052, -7.9728)
  arc A27 (61.1056, 0) -> (43.8031, -13.2366) centre (80, -42.625) ccw projected
  point P0 (0, 0)
  point P1 (48.8052, -7.9728)
  point P2 (-48.8052, -7.9728)
  dimension "d93" = 4
  dimension "d94" = 5
  dimension "d95" = 5
  dimension "d102" = 31.24
  dimension "d103" = 31.24
  dimension "d104" = 32.12
  dimension "d105" = 32.12
  dimension "d106" = 9
  constraints: 33 point on circle, 20 end point, 12 centre point, 3 line through centre, 3 point on line, 1 collinear, 1 horizontal, 13 other
  measures "d93" radial gap between concentric circles of A2 A23
  measures "d94" distance from line of L11.start L1
  measures "d95" distance from line of L13.start L12
  measures "d102" horizontal distance of point (0, 0) L9.end
  measures "d103" horizontal distance of point (0, 0) L4.end
  measures "d104" horizontal distance of point (0, 0) L9.start
  measures "d105" horizontal distance of point (0, 0) L4.start
  measures "d106" distance from line of point (0, 0) L7
extrude "Extrusión20" add sketch "Boceto20" against normal blind 20 contours A0 L13 A13 L12 | A2 L7 A23 L9 | A2 L4 A23 L5 | L10 A21 L11 A4
sketch "Boceto21" plane through (0, 0, 40) normal (0, 0, 1) x (1, 0, 0)
  line L0 (71.7129, 0) -> (52.687, 0) projected
  arc A0 (52.687, 0) -> (46.1289, -5) centre (80, -42.625) ccw projected
  line L1 (46.1289, -5) -> (48.8052, -7.9728) projected
  arc A1 (48.8052, -7.9728) -> (43.8031, -13.2366) centre (80, -42.625) ccw projected
  arc A2 (32.12, -20.4855) -> (43.8031, -13.2366) centre (27.5, 0) ccw projected
  line L2 (32.12, -20.4855) -> (31.24, -16.5835) projected
  arc A3 (9, -19.777) -> (31.24, -16.5835) centre (0, 121.9375) ccw projected
  line L3 (9, -19.777) -> (9, -23.7849) projected
  arc A4 (-9, -23.7849) -> (9, -23.7849) centre (0, 121.9375) ccw projected
  line L4 (-9, -23.7849) -> (-9, -19.777) projected
  arc A5 (-31.24, -16.5835) -> (-9, -19.777) centre (0, 121.9375) ccw projected
  line L5 (-31.24, -16.5835) -> (-32.12, -20.4855) projected
  arc A6 (-43.8031, -13.2366) -> (-32.12, -20.4855) centre (-27.5, 0) ccw projected
  arc A7 (-43.8031, -13.2366) -> (-48.8052, -7.9728) centre (-80, -42.625) ccw projected
  line L6 (-48.8052, -7.9728) -> (-46.1289, -5) projected
  arc A8 (-46.1289, -5) -> (-52.687, 0) centre (-80, -42.625) ccw projected
  line L7 (-52.687, 0) -> (-71.7129, 0) projected
  arc A9 (-71.7129, 0) -> (-70.9258, -0.9771) centre (-70.7129, 0) ccw projected
  arc A10 (-46.9085, -15.7579) -> (-70.9258, -0.9771) centre (-80, -42.625) ccw projected
  arc A11 (-46.9085, -15.7579) -> (-33, -24.3875) centre (-27.5, 0) ccw projected
  arc A12 (-33, -24.3875) -> (33, -24.3875) centre (0, 121.9375) ccw projected
  arc A13 (33, -24.3875) -> (46.9085, -15.7579) centre (27.5, 0) ccw projected
  arc A14 (70.9258, -0.9771) -> (46.9085, -15.7579) centre (80, -42.625) ccw projected
  arc A15 (70.9258, -0.9771) -> (71.7129, 0) centre (70.7129, 0) ccw projected
  arc A16 (-48.8052, -7.9728) -> (-61.1056, 0) centre (-80, -42.625) ccw projected
  arc A17 (-32.12, -20.4855) -> (-9, -23.7849) centre (0, 121.9375) ccw projected
  arc A18 (9, -23.7849) -> (32.12, -20.4855) centre (0, 121.9375) ccw projected
  arc A19 (61.1056, 0) -> (48.8052, -7.9728) centre (80, -42.625) ccw projected
  point P0 (0, 0)
extrude "Extrusión21" add sketch "Boceto21" along normal blind 55 contours A19 L1 A0 L0 | A18 L3 A3 L2 | A17 L5 A5 L4 | L7 A8 L6 A16
sketch "Boceto22" plane through (0, 0, 95) normal (0, 0, 1) x (1, 0, 0)
  arc A0 (9, -23.7849) -> (32.12, -20.4855) centre (0, 121.9375) ccw projected
  arc A1 (-9, -23.7849) -> (9, -23.7849) centre (0, 121.9375) ccw projected
  arc A2 (-32.12, -20.4855) -> (-9, -23.7849) centre (0, 121.9375) ccw projected
  arc A3 (-43.8031, -13.2366) -> (-32.12, -20.4855) centre (-27.5, 0) ccw projected
  arc A4 (-43.8031, -13.2366) -> (-48.8052, -7.9728) centre (-80, -42.625) ccw projected
  arc A5 (-48.8052, -7.9728) -> (-61.1056, 0) centre (-80, -42.625) ccw projected
  line L0 (-61.1056, 0) -> (-71.7129, 0) projected
  arc A6 (-71.7129, 0) -> (-70.9258, -0.9771) centre (-70.7129, 0) ccw projected
  arc A7 (-46.9085, -15.7579) -> (-70.9258, -0.9771) centre (-80, -42.625) ccw projected
  arc A8 (-46.9085, -15.7579) -> (-33, -24.3875) centre (-27.5, 0) ccw projected
  arc A9 (-33, -24.3875) -> (33, -24.3875) centre (0, 121.9375) ccw projected
  arc A10 (33, -24.3875) -> (46.9085, -15.7579) centre (27.5, 0) ccw projected
  arc A11 (70.9258, -0.9771) -> (46.9085, -15.7579) centre (80, -42.625) ccw projected
  arc A12 (70.9258, -0.9771) -> (71.7129, 0) centre (70.7129, 0) ccw projected
  line L1 (71.7129, 0) -> (61.1056, 0) projected
  arc A13 (61.1056, 0) -> (48.8052, -7.9728) centre (80, -42.625) ccw projected
  arc A14 (48.8052, -7.9728) -> (43.8031, -13.2366) centre (80, -42.625) ccw projected
  arc A15 (32.12, -20.4855) -> (43.8031, -13.2366) centre (27.5, 0) ccw projected
  line L2 (-9, -23.7849) -> (-9, -19.777) projected
  arc A16 (-31.24, -16.5835) -> (-9, -19.777) centre (0, 121.9375) ccw projected
  line L3 (-31.24, -16.5835) -> (-32.12, -20.4855) projected
  arc A17 (-32.12, -20.4855) -> (-9, -23.7849) centre (0, 121.9375) ccw projected
  arc A18 (-31.24, -16.5835) -> (-9, -19.777) centre (0, 121.9375) ccw projected
  line L4 (-9, -19.777) -> (-9, -27.7923)
  line L5 (9, -23.7849) -> (9, -19.777) projected
  line L6 (9, -19.777) -> (9, -27.7923)
  line L7 (31.24, -16.5835) -> (32.12, -20.4855) projected
  line L8 (31.24, -16.5835) -> (33, -24.3875)
  line L9 (-32.12, -20.4855) -> (-31.24, -16.5835) projected
  line L10 (-33, -24.3875) -> (-31.24, -16.5835)
  point P0 (0, 0)
  point P1 (32.12, -20.4855)
  point P2 (9, -23.7849)
  point P3 (-32.12, -20.4855)
  point P4 (-9, -23.7849)
  constraints: 8 end point, 2 point on circle, 1 collinear, 1 vertical
extrude "Extrusión22" add sketch "Boceto22" against normal blind 15 contours A0 L8 A9 L6 | L4 A9 L10 A2
ref_plane "Plano de trabajo2" through (0, 0, -85) normal (0, 0, 1) x (1, 0, 0)
mirror "Simetría5" about plane through (0, 0, -85) normal (0, 0, 1) of "Extrusión20", "Extrusión21", "Extrusión22"
fillet "Empalme1" radius 1.5 4 edges at (21.0689, -26.5755, 95) (-21.0689, -26.5755, 95) (21.0689, -26.5755, -265) (-21.0689, -26.5755, -265)
equation "\"d3\" = d2"
equation "\"d43\" = d42"
equation "\"d47\" = d46"
equation "\"d48\" = d46"
equation "\"d50\" = d49"
